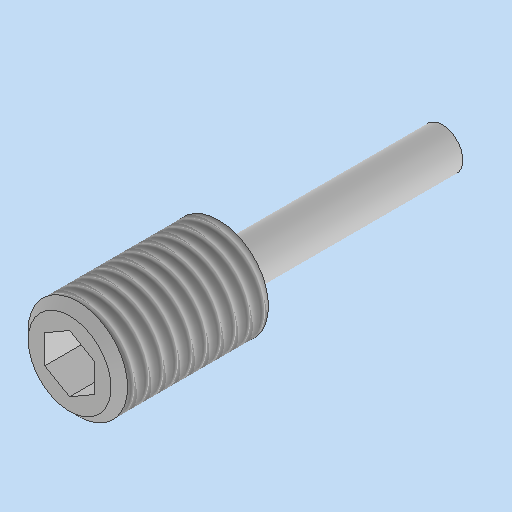
# Autodesk Inventor part: MM0937AN100_G16_511
Saved by Autodesk Inventor 2023.3 (Build 273359000, 359)
## iProperties
Created: 2024-03-15
Part Number: MM0937AN100_G16_511
Material: Generisch
Description: =<RBPARTNOTITLE2>
Document SubType Name: Modeling
Designer: FSM9BW
Mass: 20.9586 g
Surface Area: 14.0519 cm^2
Volume: 2.38166 cm^3
Density: 8.8 g/cm^3
Appearance: Vorgabe
Vendor: NORM8
RBPARTMADEOF: DIN 913 - M12x50 - 8.8 - verzinkt
RBDRAWINGMISSINGSPEC: --
AnP_Kategorie: 3
RBPARTNOTITLE2: Nacharbeit an: Gewindestifte mit Innensechskant mit Kegelstumpf
RBSURFACE: --
RBPARTNOTITLE1: rework at: Hexagon socket set screws with flat point
RBSURFACE2: --
AnP_Material: =<Material>
RBMATERIAL: --
RBMATNO: =<Part Number>
RBPARTNO: SIEHE MNR
Author: FSM9BW
Keywords: =<RBPARTMADEOF>
Comments: =<RBSURFACE2>
Revision Number: 01
Autodesk Inventor part; units mm, degrees
ref_plane "YZ Plane" through (0, 0, 0) normal (1, 0, 0) x (0, 1, 0)
ref_plane "XZ Plane" through (0, 0, 0) normal (0, 1, 0) x (-1, 0, 0)
ref_plane "XY Plane" through (0, 0, 0) normal (0, 0, 1) x (1, 0, 0)
sketch "Skizze1" plane through (0, 0, 0) normal (0, 0, 1) x (1, 0, 0)
  line L0 (0, 0) -> (0, 45)
  line L1 (0, 0) -> (-6, 0)
  line L2 (-6, 0) -> (-6, 18)
  line L3 (-6, 18) -> (-2.475, 18)
  line L4 (-2.475, 18) -> (-2.475, 45)
  line L5 (-2.475, 45) -> (0, 45)
  dimension "d2" = 18
  dimension "d3" = 45
  dimension "d4" = 4.95
  dimension "d5" = 12
  constraints: 12 end point, 4 perpendicular, 1 horizontal, 1 vertical
  measures "d2" distance of L1.end L2.end
  measures "d3" distance of L0.start L0.end
  measures "d4" diameter of L4 L0
  measures "d5" diameter of L2 L0
revolve "Umdrehung1" add sketch "Skizze1" angle 360 about axis through (0, 0, 0) along (0, 1, 0)
thread "Gewinde1" size "M12x1.75" designation "M12" class "6g" standard "ISO Metric profile" full length
sketch "Skizze2" plane through (0, 0, 0) normal (0, -1, 0) x (1, 0, 0)
  line L0 (0, 3.4641) -> (3, 1.7321)
  line L1 (3, 1.7321) -> (3, -1.7321)
  line L2 (3, -1.7321) -> (0, -3.4641)
  line L3 (0, -3.4641) -> (-3, -1.7321)
  line L4 (-3, -1.7321) -> (-3, 1.7321)
  line L5 (-3, 1.7321) -> (0, 3.4641)
  circle A0 centre (0, 0) radius 6 projected
  dimension "d9" = 6
  constraints: 12 end point, 1 coincident, 1 vertical, 13 other
  measures "d9" distance between parallel lines of L1 L4
extrude "Extrusion1" cut sketch "Skizze2" against normal blind 5 contours L0 L1 L2 L3 L4 L5
chamfer "Fase1" distance 1 angle 45 1 edges at (6, 0, 0)
